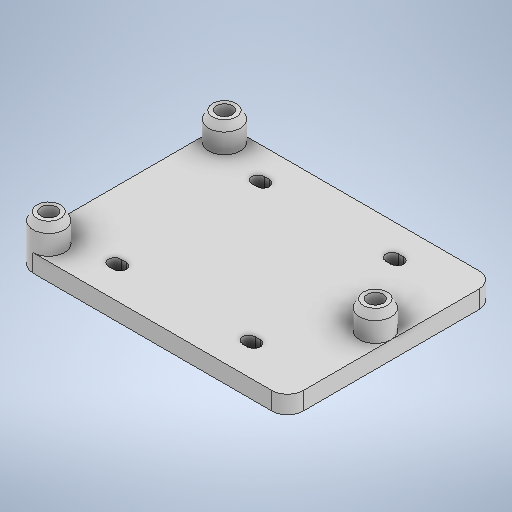
# Autodesk Inventor part: db-25_standoffs_plate_m3
Saved by Autodesk Inventor 2025.1 (Build 291241000, 241)
## iProperties
Created: 2026-06-20
Part Number: db-25_standoffs_plate_m3
Material: Generic
Document SubType Name: Modeling
Designer: Aiden
Density: 1 g/cm^3
Appearance: Default
Author: Aiden
Autodesk Inventor part; units mm, degrees
ref_plane "YZ Plane" through (0, 0, 0) normal (1, 0, 0) x (0, 1, 0)
ref_plane "XZ Plane" through (0, 0, 0) normal (0, 1, 0) x (-1, 0, 0)
ref_plane "XY Plane" through (0, 0, 0) normal (0, 0, 1) x (1, 0, 0)
sketch "Connector Hole Layout" plane through (0, 0, 0) normal (0, 1, 0) x (-1, 0, 0)
  circle A0 centre (42.9488, 7.9638) radius 1.6 construction
  circle A1 centre (-17.5388, 30.2138) radius 1.6 construction
  circle A2 centre (42.9488, 52.4638) radius 1.6 construction
  line L0 (42.9488, 7.9638) -> (42.9488, 52.4638) construction
  line L1 (41.4471, 51.9114) -> (-16.0371, 30.7661) construction
  point P0 (42.9488, 30.2138)
  dimension "d0" = 3.2
  dimension "d22" = 44.5
  dimension "d23" = 61.25
  constraints: 4 end point, 3 coincident, 1 centre point, 1 horizontal alignment, 1 midpoint, 1 vertical, 1 vertical alignment, 10 other
  measures "d0" diameter of A0
  measures "d22" distance of L0.start L0.end
sketch "Sketch8" plane through (0, 0, 0) normal (0, 1, 0) x (-1, 0, 0)
  circle A0 centre (42.9488, 7.9638) radius 1.6 construction
  circle A1 centre (42.9488, 52.4638) radius 1.6 construction
  circle A2 centre (-17.5388, 30.2138) radius 1.6 construction
  circle A3 centre (42.9488, 7.9638) radius 4
  point P0 (0, 0)
  dimension "d51" = 8
  constraints: 4 coincident, 1 centre point
  measures "d51" diameter of A3
extrude "Extrusion5" add sketch "Sketch8" along normal blind 7
sketch "Sketch9" plane through (-42.9488, 7, 7.9638) normal (0, 1, 0) x (1, 0, 0)
  point P0 (42.9488, 7.9638)
  point P1 (0, 0)
hole "Hole2" at (-42.9488, 7, 7.9638) direction (0, -1, 0) diameter 4 depth 5 tip angle 118
chamfer "Chamfer3" distance 1 distance2 2 1 edges at (-38.9488, 7, 7.9638) measured on face at (-39.4488, 7, 7.9638)
pattern_sketch "Sketch Driven Pattern1" from (-42.9488, 0, 7.9638) copies at (-42.9488, 0, 52.4638) at (17.5388, 0, 30.2138)
sketch "Sketch10" plane through (-42.9488, 0, 52.4638) normal (0, -1, 0) x (1, 0, 0)
  circle A0 centre (0, 0) radius 4 projected
  line L0 (1.3809, 3.7541) -> (61.8684, -18.4959)
  circle A1 centre (60.4875, -22.25) radius 4 projected
  line L1 (61.8684, -26.0041) -> (1.3809, -48.2541)
  circle A2 centre (0, -44.5) radius 4 projected
  line L2 (-4, -44.5) -> (-4, 0)
  circle A3 centre (0, 0) radius 4 projected
  circle A4 centre (0, -44.5) radius 4 projected
  line L3 (0, -48.5) -> (60.4875, -48.5)
  line L4 (64.4875, -44.5) -> (64.4875, 0)
  line L5 (60.4875, 4) -> (0, 4)
  line L6 (-4, 0) -> (-4, -44.5)
  circle A5 centre (60.4875, -22.25) radius 4 projected
  arc A6 (0, 4) -> (-4, 0) centre (0, 0) ccw
  arc A7 (-4, -44.5) -> (0, -48.5) centre (0, -44.5) ccw
  arc A8 (60.4875, -48.5) -> (64.4875, -44.5) centre (60.4875, -44.5) ccw
  arc A9 (64.4875, 0) -> (60.4875, 4) centre (60.4875, 0) ccw
  point P0 (42.9488, -52.4638)
  point P1 (0, 4)
  point P2 (64.4875, -22.25)
  dimension "d71" = 4
  constraints: 18 point on circle, 14 end point, 14 tangent, 4 centre point, 3 equal radius, 2 parallel, 1 horizontal, 1 perpendicular
  measures "d71" radius of A8
extrude "Extrusion6" add sketch "Sketch10" along normal blind 4.5
sketch "Sketch12" plane through (-42.9488, 0, 52.4638) normal (0, 1, 0) x (1, 0, 0)
  line L0 (12.6, 40.4) -> (13.9, 40.4) construction
  line L1 (12.6, 42) -> (13.9, 42)
  line L2 (13.9, 38.8) -> (12.6, 38.8)
  arc A0 (12.6, 42) -> (12.6, 38.8) centre (12.6, 40.4) ccw
  arc A1 (13.9, 38.8) -> (13.9, 42) centre (13.9, 40.4) ccw
  line L3 (0, 48.5) -> (60.4875, 48.5) projected
  line L4 (30.2438, 48.5) -> (30.2438, -4) construction
  line L5 (60.4875, -4) -> (0, -4) projected
  line L6 (-4, 0) -> (-4, 44.5) projected
  line L7 (64.4875, 44.5) -> (64.4875, 22.25) projected
  line L8 (-4, 22.25) -> (64.4875, 22.25) construction
  line L9 (47.8875, 40.4) -> (46.5875, 40.4) construction
  line L10 (47.8875, 42) -> (46.5875, 42)
  line L11 (46.5875, 38.8) -> (47.8875, 38.8)
  arc A2 (47.8875, 38.8) -> (47.8875, 42) centre (47.8875, 40.4) ccw
  arc A3 (46.5875, 42) -> (46.5875, 38.8) centre (46.5875, 40.4) ccw
  line L12 (12.6, 4.1) -> (13.9, 4.1) construction
  line L13 (12.6, 2.5) -> (13.9, 2.5)
  line L14 (13.9, 5.7) -> (12.6, 5.7)
  arc A4 (12.6, 5.7) -> (12.6, 2.5) centre (12.6, 4.1) ccw
  arc A5 (13.9, 2.5) -> (13.9, 5.7) centre (13.9, 4.1) ccw
  line L15 (46.5875, 5.7) -> (47.8875, 5.7)
  line L16 (47.8875, 4.1) -> (46.5875, 4.1) construction
  arc A6 (47.8875, 2.5) -> (47.8875, 5.7) centre (47.8875, 4.1) ccw
  line L17 (47.8875, 2.5) -> (46.5875, 2.5)
  arc A7 (46.5875, 5.7) -> (46.5875, 2.5) centre (46.5875, 4.1) ccw
  point P0 (42.9488, 52.4638)
  point P1 (13.25, 40.4)
  point P2 (13.25, 38.8)
  point P3 (13.25, 42)
  point P4 (11, 40.4)
  point P5 (15.5, 40.4)
  point P6 (47.2375, 40.4)
  point P7 (47.2375, 38.8)
  point P8 (47.2375, 42)
  point P9 (49.4875, 40.4)
  point P10 (44.9875, 40.4)
  point P11 (13.25, 4.1)
  point P12 (13.25, 5.7)
  point P13 (13.25, 2.5)
  point P14 (11, 4.1)
  point P15 (15.5, 4.1)
  point P16 (47.2375, 5.7)
  point P17 (49.4875, 4.1)
  point P18 (47.2375, 4.1)
  point P19 (44.9875, 4.1)
  point P20 (47.2375, 2.5)
  dimension "d72" = 3.2
  dimension "d73" = 4.5
  dimension "d74" = 6.5
  dimension "d75" = 15
  constraints: 36 end point, 33 symmetric about line, 18 point on circle, 8 centre point, 6 midpoint, 4 tangent, 1 horizontal, 1 parallel, 1 perpendicular, 6 other
  measures "d72" distance of point (13.25, 38.8) point (13.25, 42)
  measures "d73" distance of point (11, 40.4) point (15.5, 40.4)
  measures "d74" distance from line of L3 point (13.25, 42)
  measures "d75" distance from line of L6 point (11, 40.4)
extrude "Extrusion8" cut sketch "Sketch12" against normal blind 4.5
body "Solid2"
